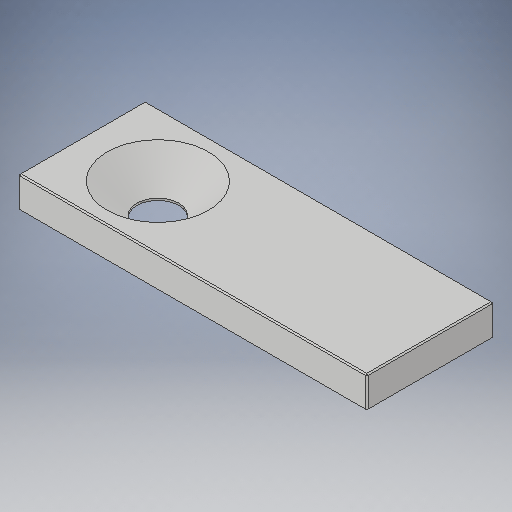
# Autodesk Inventor part: BT027_thutrn22_26
Saved by Autodesk Inventor 2025.3 (Build 293356000, 356)
## iProperties
Company: HTBLA Kaindorf
RuleStatus: InUse
Created: 2026-08-19
Part Number: BT027_thutrn22_26
Project: Biegeroboter
Material: Generisch
Description: gehaeuse_lasche_deckel
Document SubType Name: Modeling
Designer: thutrn22
Density: 1 g/cm^3
Appearance: Vorgabe
Mass: 4.98469 g
Surface Area: 29.1865 cm^2
Volume: 4.98469 cm^3
AfterDocNew0: iProperties-Editor_aufrufen
Author: trist
Keywords: 2026
Autodesk Inventor part; units mm, degrees
ref_plane "YZ Plane" through (0, 0, 0) normal (1, 0, 0) x (0, 1, 0)
ref_plane "XZ Plane" through (0, 0, 0) normal (0, 1, 0) x (-1, 0, 0)
ref_plane "XY Plane" through (0, 0, 0) normal (0, 0, 1) x (1, 0, 0)
sketch "Skizze3" plane through (0, 0, 0) normal (0, 0, 1) x (1, 0, 0)
  line L0 (-14, 0) -> (14, 0) projected
  line L1 (0, -38.5) -> (0, 38.5) projected
  line L2 (-10, 27.5) -> (10, 27.5)
  line L3 (10, 27.5) -> (10, -27.5)
  line L4 (10, -27.5) -> (-10, -27.5)
  line L5 (-10, -27.5) -> (-10, 27.5)
  circle A0 centre (0, -16) radius 8
  point P0 (0, 0)
  dimension "d4" = 20
  dimension "d5" = 55
  dimension "d6" = 16
  dimension "d7" = 43.5
  constraints: 8 end point, 2 parallel, 1 centre point, 1 horizontal, 1 perpendicular, 1 point on line, 2 other
  measures "d4" distance of L3.end L4.end
  measures "d5" distance of L2.end L3.end
  measures "d6" diameter of A0
  measures "d7" distance from line of L2 A0.centre
extrude "Extrusion3" add sketch "Skizze3" along normal blind 5
sketch "Skizze4" plane through (0, 0, 5) normal (0, 0, 1) x (1, 0, 0)
  line L0 (10, 27.5) -> (-10, 27.5) projected
  line L1 (10, -27.5) -> (10, 27.5) projected
  point P0 (0, 0)
  point P1 (0, -15.5)
  dimension "d10" = 43
  dimension "d11" = 10
  measures "d10" distance from line of point (0, -15.5) L0
  measures "d11" distance from line of L1 point (0, -15.5)
hole "Bohrung1" at (0, -15.5, 5) direction (0, 0, -1) diameter 6.647 end through all countersink diameter 16 countersink angle 90 thread size "M8x1.25" class "6H" standard "ISO Metric profile"
chamfer "Fasen1" distance 0.2 angle 45 12 edges at (10, 0, 5) (0, 27.5, 5) (10, 0, 0) (10, 27.5, 2.5) (0, 27.5, 0) (-10, 0, 5) (-10, 27.5, 2.5) (-10, 0, 0) (0, -27.5, 5) (-10, -27.5, 2.5) (10, -27.5, 2.5) (0, -27.5, 0)
